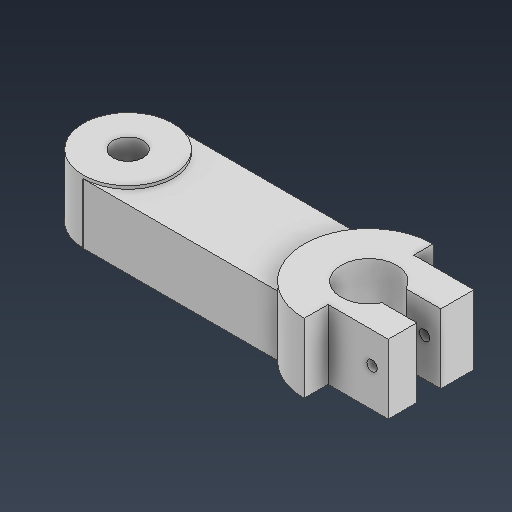
# Autodesk Inventor part: Brazo
Saved by Autodesk Inventor 2026.4 (Build 304435000, 435)
## iProperties
Created: 2026-09-06
Part Number: Brazo
Material: Generic
Document SubType Name: Modeling
Designer: YmCris
Density: 1 g/cm^3
Appearance: Default
Author: YmCris
Autodesk Inventor part; units mm, degrees
ref_plane "YZ Plane" through (0, 0, 0) normal (1, 0, 0) x (0, 1, 0)
ref_plane "XZ Plane" through (0, 0, 0) normal (0, 1, 0) x (-1, 0, 0)
ref_plane "XY Plane" through (0, 0, 0) normal (0, 0, 1) x (1, 0, 0)
sketch "Sketch2" plane through (0, 0, 0) normal (0, 1, 0) x (-1, 0, 0)
  line L0 (-20, -7.5) -> (20, -7.5)
  line L1 (20, -7.5) -> (20, 7.5)
  line L2 (20, 7.5) -> (-20, 7.5)
  line L3 (-20, 7.5) -> (-20, -7.5)
  line L4 (-20, -7.5) -> (20, 7.5) construction
  line L5 (20, -7.5) -> (-20, 7.5) construction
  point P0 (0, 0)
  dimension "d4" = 40
  dimension "d5" = 15
  constraints: 12 end point, 2 midpoint, 2 parallel, 1 horizontal, 1 perpendicular
  measures "d4" distance of L2.end L1.end
  measures "d5" distance of L1.end L0.end
extrude "Extrusion2" add sketch "Sketch2" along normal blind 10
sketch "Sketch3" plane through (0, 10, 0) normal (0, 1, 0) x (1, 0, 0)
  line L0 (-20, 7.5) -> (-20, -7.5) projected
  circle A0 centre (-20, 0) radius 7.4591
  point P0 (0, 0)
  point P1 (-20, -7.4591)
  point P2 (-20, 7.4591)
  constraints: 1 centre point, 1 midpoint
extrude "Extrusion3" add sketch "Sketch3" against normal blind 10 contours L0 A0 picked at (-23.6237, 0.5845)
sketch "Sketch4" plane through (0, 10, 0) normal (0, 1, 0) x (1, 0, 0)
  circle A0 centre (-20, 0) radius 7.4591
  point P0 (0, 0)
  constraints: 1 centre point
extrude "Extrusion4" add sketch "Sketch4" along normal blind 0.5
sketch "Sketch5" plane through (-20, 10.5, 0) normal (0, 1, 0) x (1, 0, 0)
  circle A0 centre (0, 0) radius 2.5
  point P0 (20, 0)
  dimension "d12" = 5
  constraints: 1 centre point
  measures "d12" diameter of A0
extrude "Extrusion5" cut sketch "Sketch5" against normal blind 10.5
sketch "Sketch6" plane through (0, 10, 0) normal (0, 1, 0) x (1, 0, 0)
  line L0 (20, -7.5) -> (20, 7.5) projected
  arc A0 (20, 10.7151) -> (20, -10.7151) centre (20, 0) ccw
  line L1 (20, -10.7151) -> (20, 10.7151)
  point P0 (0, 0)
  constraints: 2 end point, 2 point on circle, 1 centre point, 1 midpoint
extrude "Extrusion6" add sketch "Sketch6" along normal blind 1.5
sketch "Sketch7" plane through (0, 0, 0) normal (0, -1, 0) x (1, 0, 0)
  line L0 (20, 7.5) -> (20, -7.5) projected
  arc A0 (20, 10.7151) -> (20, -10.7151) centre (20, 0) ccw
  line L1 (20, 10.7151) -> (20, -10.7151)
  point P0 (0, 0)
  constraints: 2 end point, 2 point on circle, 2 point on line, 1 centre point, 1 midpoint, 1 vertical
extrude "Extrusion7" add sketch "Sketch7" against normal blind 10
sketch "Sketch8" plane through (20, 0, 10.7151) normal (1, 0, 0) x (0, 0, -1)
  line L0 (21.4302, 11.5) -> (0, 11.5) projected
  line L1 (18.2151, 0) -> (18.2151, 10) projected
  line L2 (3.9778, 11.5) -> (18.2151, 11.5)
  line L3 (18.2151, 11.5) -> (18.2151, 0)
  line L4 (18.2151, 0) -> (3.9778, 0)
  line L5 (3.9778, 0) -> (3.9778, 11.5)
  point P0 (10.7151, 0)
  constraints: 8 end point, 2 parallel, 1 horizontal, 1 perpendicular, 1 point on line
extrude "Extrusion8" add sketch "Sketch8" along normal blind 10
sketch "Sketch9" plane through (0, 11.5, 0) normal (0, 1, 0) x (1, 0, 0)
  circle A0 centre (20.0444, 0) radius 4.6233
  point P0 (0, 0)
  constraints: 1 centre point
extrude "Extrusion9" cut sketch "Sketch9" against normal blind 11.5
sketch "Sketch10" plane through (20, 0, 6.7373) normal (0, 0, 1) x (1, 0, 0)
  circle A0 centre (7.3035, 6.346) radius 0.8659
  point P0 (-20, 0)
  constraints: 1 centre point
extrude "Extrusion10" cut sketch "Sketch10" against normal blind 15.25
sketch "Sketch11" plane through (0, 11.5, 0) normal (0, 1, 0) x (1, 0, 0)
  line L0 (24.2125, -2.0004) -> (30, -2.0004)
  line L1 (30, -6.7373) -> (30, 7.5) projected
  circle A0 centre (20.0444, 0) radius 4.6233 projected
  line L2 (24.2125, 2.0004) -> (30.0493, 2.0004)
  arc A1 (24.2125, -2.0004) -> (24.2125, 2.0004) centre (20.0444, 0) ccw
  point P0 (0, 0)
  point P1 (30, 2.0033)
  point P2 (30, 2.0004)
  constraints: 4 end point, 3 point on circle, 1 centre point, 1 concentric, 1 horizontal, 1 perpendicular, 1 point on line
extrude "Extrusion13" cut sketch "Sketch11" against normal blind 11.5 contours A0 L2 L1 L0
body "Solid2"
